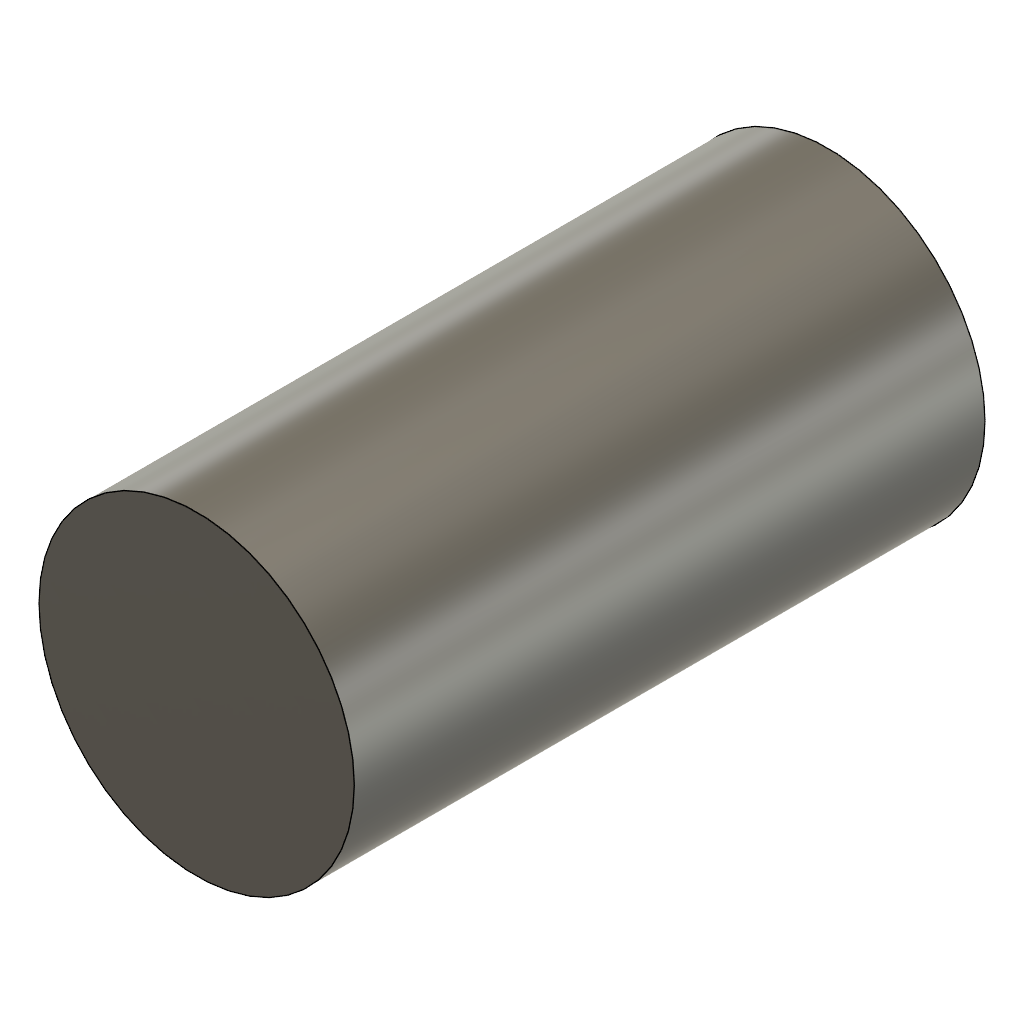
first_restored (Autodesk Fusion 360 design; units mm, degrees)
part number: 2026-11-27-17-29-22-457
Autodesk Fusion 360 part; units mm, degrees
sketch "CircularProfile" plane through (0, 0, 0) normal (0, 0, 1) x (1, 0, 0)
  circle A0 centre (7, -11) radius 13
extrude "OffsetTwoSides" add sketch "CircularProfile" along normal blind 23 and the other way blind 29 from surface at 7
